StaticScrewTest (Autodesk Fusion 360 design; units mm, degrees)
Autodesk Fusion 360 part; units mm, degrees
note: some values were not read from the file. Set by a fixed rule: which face or edge a step refers to.
sketch "Sketch1" plane through (0, 0, 0) normal (0, 1, 0) x (1, 0, 0)
  circle A0 centre (0, 0) radius 5
  circle A1 centre (0, 0) radius 5.15
  circle A2 centre (0, 0) radius 6.5
  dimension "d1" = 10
  dimension "d2" = 10.3
  dimension "d3" = 13
  constraint coincident A0.centre A1.centre
  constraint concentric A1 A2
  measures "d1" diameter of A0
  measures "d2" diameter of A1
  measures "d3" diameter of A2
sketch "Sketch2" plane through (0, 0, 0) normal (0, 0, 1) x (1, 0, 0)
  line L0 (0, 0) -> (-5, 0)
  line L1 (-5, 0) -> (-5.15, 0)
  line L2 (-5.15, 0) -> (-6.5, 0)
  line L3 (-3.5, 5) -> (-5, 0)
  line L4 (-3.5, 5) -> (-5, 10)
  line L5 (-5.15, 0) -> (-3.65, 5)
  line L6 (-5, 10) -> (-5.15, 10)
  line L7 (-5.15, 10) -> (-3.65, 5)
  line L8 (-5.15, 0) -> (-6.5, 0)
  line L9 (-6.5, 0) -> (-6.5, 10)
  line L10 (-6.5, 10) -> (-5.15, 10)
  line L11 (-5, 0) -> (0, 0)
  line L12 (0, 0) -> (0, 10)
  line L13 (0, 10) -> (-5, 10)
  dimension "d6" = 0.15
  dimension "d9" = 10
  dimension "d11" = 0.15
  dimension "d13" = 0.15
  constraint coincident L0.start L11.end
  constraint horizontal L0
  constraint parallel L0 L1
  constraint horizontal L2
  constraint horizontal L6
  constraint parallel L2 L8
  constraint perpendicular L8 L9
  constraint perpendicular L9 L10
  constraint parallel L0 L11
  constraint perpendicular L0 L12
  measures "d6" distance of L0.end L1.end
  measures "d9" distance of L0.end L4.end
  measures "d11" distance of L3.start L5.end
  measures "d13" distance of L4.end L6.end
extrude "Extrude1" add sketch "Sketch1" along normal blind 5 draft -16.7 contours A0 makes body 1
extrude "Extrude2" add 1 faces at (2.0381, 5, 0.7315) along direction (0, 1, 0) blind 5 draft 16.7 on bodies 1 bodies 1
extrude "Extrude3" add sketch "Sketch1" along normal blind 5 draft 16.3 separate body contours A2 makes body 2
extrude "Extrude4" add 1 faces at (6.5077, 5, 0.3956) along direction (0, 1, 0) blind 5 draft -16.3 on bodies 2 bodies 2
sketch "Sketch3" plane through (0, 10, 0) normal (0, 1, 0) x (-1, 0, 0)
  circle A0 centre (0, 0) radius 5.15
  circle A1 centre (0, 0) radius 6.5
fillet "Fillet1" radius 3.75 1 edges at (-7.4233, 5, -2.8792) on bodies 2
copy_body "Body->Comp1" bodies 1 removing the originals makes body 3 in component "Component"
copy_body "Body->Comp2" bodies 2 removing the originals makes body 4 in component "Component'"
sketch "Sketch4" plane through (0, 10, 0) normal (0, 1, 0) x (-1, 0, 0)
  circle A0 centre (0, 0) radius 5
  circle A1 centre (0, 0) radius 7.856
  circle A2 centre (0, 0) radius 5.7836
  constraint coincident A0.centre A1.centre
  constraint concentric A0 A2
extrude "Extrude1'" add sketch "Sketch4" against normal blind 10 contours A1 bodies 4 in component "Component'"
thread "Thread1" "ISO Metric profile 16.0 M16x2 6g" major diameter 15.822 minor diameter 13.534 pitch 2 angle 60 modelled right hand crest width 0.2847 on face at (-7.8462, 3.3333, -0.3916) crest through (-7.911, 10.5, 0) on bodies 4 in component "Component'"
extrude "Extrude1''" add 1 faces at (1.3101, 0, 1.9935) along direction (0, -1, 0) blind 4 on bodies 3 bodies 3 in component "Component"
sketch "Sketch5" plane through (0, -4, 0) normal (0, -1, 0) x (1, 0, 0)
  circle A0 centre (0, 0) radius 5
  line L0 (1, -7.5) -> (-1, -7.5)
  line L1 (-1, -7.5) -> (-1, 7.5)
  line L2 (-1, 7.5) -> (1, 7.5)
  line L3 (1, 7.5) -> (1, -7.5)
  line L4 (1, -7.5) -> (-1, 7.5) construction
  line L5 (-1, -7.5) -> (1, 7.5) construction
  constraint perpendicular L0 L1
  constraint parallel L0 L2
  constraint parallel L1 L3
  constraint horizontal L0
  constraint coincident L4 A0.centre
  constraint coincident L5 A0.centre
  constraint coincident A0.centre origin
extrude "Extrude2'" cut sketch "Sketch5" against normal blind 4 contours A0 L3 | A0 L1 bodies 3 in component "Component"
sketch "Sketch6" plane through (0, -4, 0) normal (0, -1, 0) x (1, 0, 0)
  line L0 (-1, 4.899) -> (-1, -4.899)
  arc A0 (-1, -4.899) -> (1, -4.899) centre (0, 0) ccw
  line L1 (1, -4.899) -> (1, 4.899)
  arc A1 (1, 4.899) -> (-1, 4.899) centre (0, 0) ccw
  line L2 (1, -7) -> (-1, -7)
  line L3 (-1, -7) -> (-1, 7)
  line L4 (-1, 7) -> (1, 7)
  line L5 (1, 7) -> (1, -7)
  line L6 (1, -7) -> (-1, 7) construction
  line L7 (-1, -7) -> (1, 7) construction
  constraint perpendicular L2 L3
  constraint parallel L2 L4
  constraint parallel L3 L5
  constraint horizontal L2
  constraint coincident L6 A0.centre
  constraint coincident L7 A0.centre
  constraint coincident A0.centre A1.centre
extrude "Extrude3'" add sketch "Sketch6" against normal blind 2 contours A1 L3 L4 L5 | A0 L2 L3 L5 bodies 3 in component "Component"
chamfer "Chamfer1" distance 2 angle 45 2 edges at (0, -2, -5) (0, -2, 5) tangent chain off on bodies 3 in component "Component"
extrude "Extrude4'" cut 4 faces at (0.8893, -2, 6.9654) (-0.8893, -2, 6.9654) (0.8893, -2, -6.9654) (-0.8893, -2, -6.9654) along direction (0, -1, 0) blind 2 on bodies 3 bodies 3 in component "Component"
sketch "Sketch7" plane through (0, -4, 0) normal (0, -1, 0) x (1, 0, 0)
  arc A0 (-1, -6.9282) -> (1, -6.9282) centre (0, 0) ccw
  line L0 (1, -6.9282) -> (1, 6.9282)
  arc A1 (1, 6.9282) -> (-1, 6.9282) centre (0, 0) ccw
  line L1 (-1, 6.9282) -> (-1, -6.9282)
  line L2 (1, -8) -> (-1, -8)
  line L3 (-1, -8) -> (-1, 8)
  line L4 (-1, 8) -> (1, 8)
  line L5 (1, 8) -> (1, -8)
  line L6 (1, -8) -> (-1, 8) construction
  line L7 (-1, -8) -> (1, 8) construction
  constraint perpendicular L2 L3
  constraint parallel L2 L4
  constraint parallel L3 L5
  constraint horizontal L2
  constraint coincident L6 A0.centre
  constraint coincident L7 A0.centre
  constraint coincident A0.centre A1.centre
extrude "Extrude5" add sketch "Sketch7" against normal blind 2 contours A0 L2 L3 L5 | A1 L3 L4 L5 bodies 3 in component "Component"
sketch "Sketch8" plane through (1, 0, 0) normal (1, 0, 0) x (0, 0, -1)
  spline S0 degree 2 poles (4.899, 0) (5.7445, -0.8284) (6.9282, -2) knots 0 0 0 0.284917 0.284917 0.284917 weights 1 1.014612 1
  line L0 (4.899, 0) -> (-4.899, 0)
  spline S1 degree 2 poles (-6.9282, -2) (-5.7445, -0.8284) (-4.899, 0) knots 0 0 0 0.284917 0.284917 0.284917 weights 1 1.014612 1
  line L1 (-6.9282, -2) -> (-8, -2)
  line L2 (-8, -2) -> (-8, -4)
  line L3 (-8, -4) -> (8, -4)
  line L4 (8, -4) -> (8, -2)
  line L5 (8, -2) -> (6.9282, -2)
  line L6 (-4.899, 0) -> (-8, -3.5)
  line L7 (4.899, 0) -> (8, -3.5)
  line L8 (-8, -3.5) -> (-8.7026, -3.5597)
  line L9 (-8.7026, -3.5597) -> (-8.3513, -1.589)
  line L10 (-8.3513, -1.589) -> (-5.3631, 0)
  line L11 (-5.3631, 0) -> (-4.899, 0)
  line L12 (4.899, 0) -> (6.8123, 0)
  line L13 (6.8123, 0) -> (8.8271, -2.5421)
  line L14 (8.8271, -2.5421) -> (8, -3.5)
  constraint coincident L0.end S1.end
  constraint coincident L2 L6.end
  constraint coincident S0.start L0.start
  constraint coincident L4 L7.end
  constraint parallel L0 L11
  constraint parallel L0 L12
extrude "Extrude6" cut sketch "Sketch8" against normal blind 2 contours S0 L4 L5 L12 L13 L14 | S0 L4 L5 L7 | S1 L1 L2 L6 | S1 L1 L2 L8 L9 L10 L11 bodies 3 in component "Component"
sketch "Sketch9" plane through (0, 10, 0) normal (0, 1, 0) x (-1, 0, 0)
  circle A0 centre (0, 0) radius 5
  circle A1 centre (0, 0) radius 5
  circle A2 centre (0, 0) radius 7.9247
  circle A3 centre (0, 0) radius 5.075
  dimension "d42" = 10.15
  constraint concentric A0 A1
  constraint concentric A1 A2
  constraint concentric A2 A3
  measures "d42" diameter of A3
extrude "Extrude4''" add sketch "Sketch9" along normal blind 3 contours A2 bodies 4 in component "Component'"
copy_body "CutPasteBodies1" bodies 3 removing the originals makes body 5 in component "Component'"
extrude "Extrude5'" add sketch "Sketch9" along normal blind 3 contours A0 A1 bodies 5 in component "Component'"
component "Component" placed x (1, 0, 0) y (0, 1, 0) z (0, 0, 1) at (0, 0, 0)
component "Component'" placed x (1, 0, 0) y (0, 1, 0) z (0, 0, 1) at (0, 0, 0)
